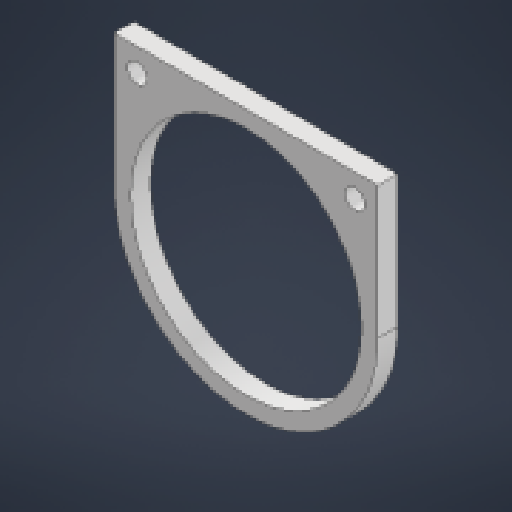
# Autodesk Inventor part: Moter_Fix_Back
Saved by Autodesk Inventor 2027.1 (Build 311270010, 270A)
## iProperties
Created: 2026-11-11
Part Number: Moter_Fix_Back
Material: 一般
Document SubType Name: Modeling
Designer: takuya
Density: 1 g/cm^3
Appearance: 既定
Author: takuya
Autodesk Inventor part; units mm, degrees
ref_plane "YZ Plane" through (0, 0, 0) normal (1, 0, 0) x (0, 1, 0)
ref_plane "XZ Plane" through (0, 0, 0) normal (0, 1, 0) x (-1, 0, 0)
ref_plane "XY Plane" through (0, 0, 0) normal (0, 0, 1) x (1, 0, 0)
sketch "スケッチ1" plane through (0, 0, 0) normal (0, 0, 1) x (1, 0, 0)
  circle A0 centre (0, 0) radius 17.5 projected
  line L0 (-20, 20) -> (20, 20) projected
  line L1 (-20, 0) -> (-20, 20) projected
  arc A1 (-20, 0) -> (20, 0) centre (0, 0) ccw projected
  line L2 (20, 20) -> (20, 0) projected
  circle A2 centre (0, 0) radius 16 projected
  circle A3 centre (-16.5, 16.5) radius 1.5 projected
  circle A4 centre (16.5, 16.5) radius 1.5 projected
  point P0 (0, 0)
extrude "押し出し1" add sketch "スケッチ1" against normal blind 3 contours L0 L2 A1 L1
